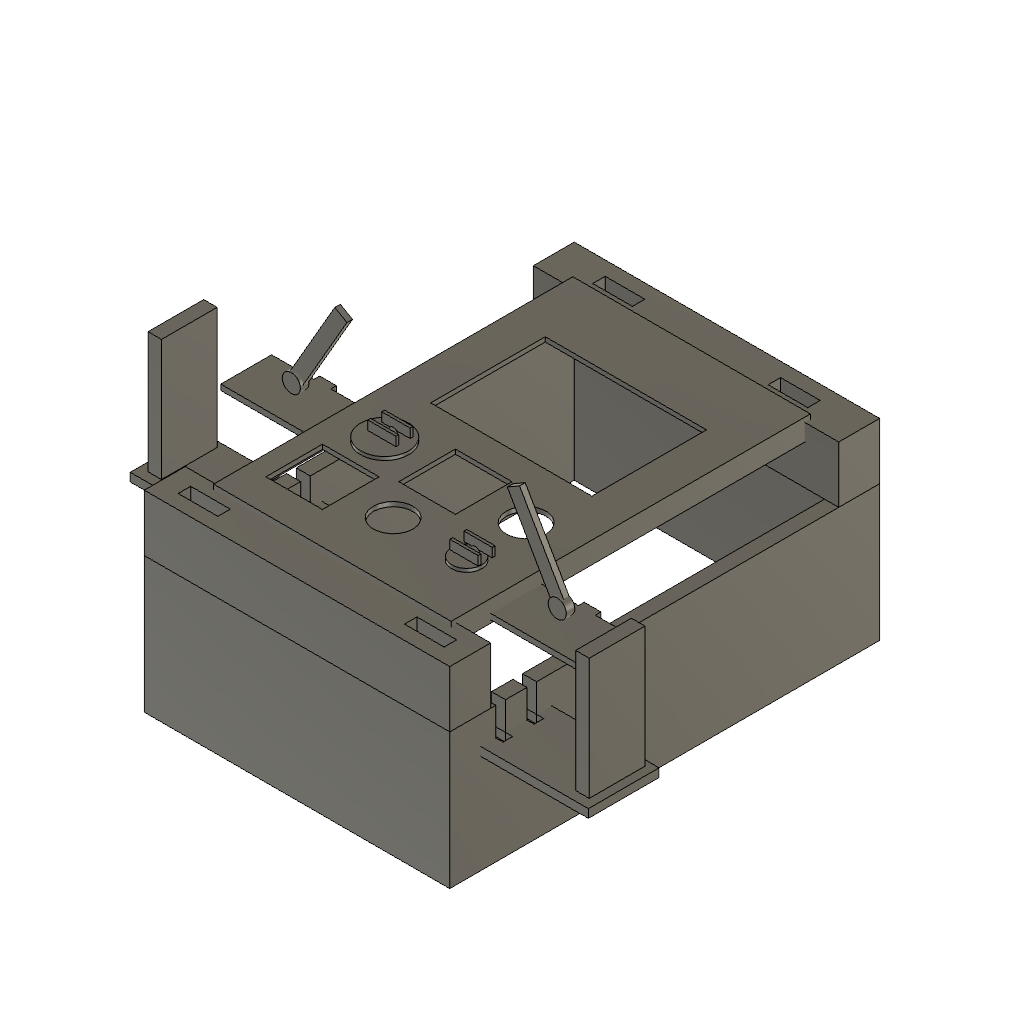
VS-MGE20_Case_SG90_square20 (Autodesk Fusion 360 design; units mm, degrees)
Autodesk Fusion 360 part; units mm, degrees
(part 1 of 2)
sketch "スケッチ1" plane through (0, 0, 0) normal (0, 0, 1) x (1, 0, 0) in component "VS-MGE20 Case Assembly"
  line L0 (-42, -63.5) -> (42, -63.5)
  line L1 (42, -63.5) -> (42, 63.5)
  line L2 (42, 63.5) -> (-42, 63.5)
  line L3 (-42, 63.5) -> (-42, -63.5)
  line L4 (-28.5, -0.25) -> (28.5, -0.25)
  line L5 (28.5, -0.25) -> (28.5, 40.25)
  line L6 (28.5, 40.25) -> (-28.5, 40.25)
  line L7 (-28.5, 40.25) -> (-28.5, -0.25)
  circle A0 centre (-25, -20) radius 8
  circle A1 centre (26, -42) radius 4.8
  line L8 (-33, -34.55) -> (-16, -34.55)
  line L9 (-16, -34.55) -> (-16, -33.45)
  line L10 (-16, -33.45) -> (-33, -33.45)
  line L11 (-33, -33.45) -> (-33, -34.55)
  line L12 (-33, -37.55) -> (-16, -37.55)
  line L13 (-16, -37.55) -> (-16, -36.45)
  line L14 (-16, -36.45) -> (-33, -36.45)
  line L15 (-33, -36.45) -> (-33, -37.55)
  line L16 (-33, -40.55) -> (-16, -40.55)
  line L17 (-16, -40.55) -> (-16, -39.45)
  line L18 (-16, -39.45) -> (-33, -39.45)
  line L19 (-33, -39.45) -> (-33, -40.55)
  line L20 (-33, -43.55) -> (-16, -43.55)
  line L21 (-16, -43.55) -> (-16, -42.45)
  line L22 (-16, -42.45) -> (-33, -42.45)
  line L23 (-33, -42.45) -> (-33, -43.55)
  line L24 (-33, -46.55) -> (-16, -46.55)
  line L25 (-16, -46.55) -> (-16, -45.45)
  line L26 (-16, -45.45) -> (-33, -45.45)
  line L27 (-33, -45.45) -> (-33, -46.55)
  line L28 (-33, -49.55) -> (-16, -49.55)
  line L29 (-16, -49.55) -> (-16, -48.45)
  line L30 (-16, -48.45) -> (-33, -48.45)
  line L31 (-33, -48.45) -> (-33, -49.55)
extrude "1.6 mm face plate" add sketch "スケッチ1" along normal blind 1.6 makes body 1 in component "VS-MGE20 Case Assembly"
sketch "スケッチ2" plane through (0, 0, 0) normal (0, 0, 1) x (1, 0, 0) in component "VS-MGE20 Case Assembly"
  line L0 (-42, -63.5) -> (42, -63.5)
  line L1 (42, -63.5) -> (42, 63.5)
  line L2 (42, 63.5) -> (-42, 63.5)
  line L3 (-42, 63.5) -> (-42, -63.5)
  line L4 (-40.5, -62) -> (40.5, -62)
  line L5 (40.5, -62) -> (40.5, 62)
  line L6 (40.5, 62) -> (-40.5, 62)
  line L7 (-40.5, 62) -> (-40.5, -62)
extrude "6 mm rear retaining rim" add sketch "スケッチ2" against normal blind 6 bodies 1 in component "VS-MGE20 Case Assembly"
ref_plane "作業平面1" through (0, 0, -68) normal (0, 0, 1) x (1, 0, 0) in component "VS-MGE20 Case Assembly"
sketch "スケッチ3" plane through (0, 0, -68) normal (0, 0, 1) x (1, 0, 0) in component "VS-MGE20 Case Assembly"
  line L0 (-54, -76) -> (54, -76)
  line L1 (54, -76) -> (54, 76)
  line L2 (54, 76) -> (-54, 76)
  line L3 (-54, 76) -> (-54, -76)
  line L4 (-49, -71) -> (49, -71)
  line L5 (49, -71) -> (49, 71)
  line L6 (49, 71) -> (-49, 71)
  line L7 (-49, 71) -> (-49, -71)
ref_plane "作業平面2" through (0, 0, -20) normal (0, 0, 1) x (1, 0, 0) in component "VS-MGE20 Case Assembly"
sketch "スケッチ4" plane through (0, 0, -20) normal (0, 0, 1) x (1, 0, 0) in component "VS-MGE20 Case Assembly"
  line L0 (-54, 61.5) -> (54, 61.5)
  line L1 (54, 61.5) -> (54, 76)
  line L2 (54, 76) -> (-54, 76)
  line L3 (-54, 76) -> (-54, 61.5)
  line L4 (-54, -76) -> (54, -76)
  line L5 (54, -76) -> (54, -61.5)
  line L6 (54, -61.5) -> (-54, -61.5)
  line L7 (-54, -61.5) -> (-54, -76)
extrude "Top and bottom support bridges" add sketch "スケッチ4" along normal blind 20 separate body contours L0 L1 L2 L3 makes body 2 in component "VS-MGE20 Case Assembly"
ref_plane "作業平面3" through (0, 0, -23) normal (0, 0, 1) x (1, 0, 0) in component "VS-MGE20 Case Assembly"
sketch "スケッチ5" plane through (0, 0, -23) normal (0, 0, 1) x (1, 0, 0) in component "VS-MGE20 Case Assembly"
  line L0 (-90, -24) -> (-44, -24)
  line L1 (-44, -24) -> (-44, 28)
  line L2 (-44, 28) -> (-90, 28)
  line L3 (-90, 28) -> (-90, -24)
  line L4 (44, -46) -> (90, -46)
  line L5 (90, -46) -> (90, 6)
  line L6 (90, 6) -> (44, 6)
  line L7 (44, 6) -> (44, -46)
  circle A0 centre (-84, -18) radius 1.7
  circle A1 centre (-50, 20) radius 1.7
  circle A2 centre (-84, -56) radius 1.7
  circle A3 centre (-50, -22) radius 1.7
  circle A4 centre (84, -40) radius 1.7
  circle A5 centre (50, 2) radius 1.7
  circle A6 centre (84, -78) radius 1.7
  circle A7 centre (50, -44) radius 1.7
ref_plane "作業平面4" through (0, 0, -20) normal (0, 0, 1) x (1, 0, 0) in component "VS-MGE20 Case Assembly"
sketch "スケッチ6" plane through (0, 0, -20) normal (0, 0, 1) x (1, 0, 0) in component "VS-MGE20 Case Assembly"
  line L0 (-54, -76) -> (54, -76)
  line L1 (54, -76) -> (54, -61.5)
  line L2 (54, -61.5) -> (-54, -61.5)
  line L3 (-54, -61.5) -> (-54, -76)
ref_plane "作業平面5" through (0, 0, -23) normal (0, 0, 1) x (1, 0, 0) in component "VS-MGE20 Case Assembly"
sketch "スケッチ7" plane through (0, 0, -23) normal (0, 0, 1) x (1, 0, 0) in component "VS-MGE20 Case Assembly"
  line L0 (44, -46) -> (90, -46)
  line L1 (90, -46) -> (90, 6)
  line L2 (90, 6) -> (44, 6)
  line L3 (44, 6) -> (44, -46)
  circle A0 centre (84, -40) radius 1.7
  circle A1 centre (50, 2) radius 1.7
  circle A2 centre (84, -78) radius 1.7
  circle A3 centre (50, -44) radius 1.7
ref_plane "作業平面6" through (0, 0, -19.7) normal (0, 0, 1) x (1, 0, 0) in component "VS-MGE20 Case Assembly"
sketch "スケッチ8" plane through (0, 0, -19.7) normal (0, 0, 1) x (1, 0, 0) in component "VS-MGE20 Case Assembly"
  line L0 (-87.35, -20) -> (-46.65, -20)
  line L1 (-46.65, -20) -> (-46.65, 22.9)
  line L2 (-46.65, 22.9) -> (-87.35, 22.9)
  line L3 (-87.35, 22.9) -> (-87.35, -20)
ref_plane "作業平面7" through (0, 0, -19.7) normal (0, 0, 1) x (1, 0, 0) in component "VS-MGE20 Case Assembly"
sketch "スケッチ9" plane through (0, 0, -19.7) normal (0, 0, 1) x (1, 0, 0) in component "VS-MGE20 Case Assembly"
  line L0 (46.65, -42) -> (87.35, -42)
  line L1 (87.35, -42) -> (87.35, 0.9)
  line L2 (87.35, 0.9) -> (46.65, 0.9)
  line L3 (46.65, 0.9) -> (46.65, -42)
ref_plane "作業平面8" through (0, 18, 0) normal (0, 1, 0) x (0, 0, 1) in component "VS-MGE20 Case Assembly"
sketch "スケッチ10" plane through (0, 18, 0) normal (0, 1, 0) x (1, 0, 0) in component "VS-MGE20 Case Assembly"
  line L0 (-55.3119, -8.8999) -> (-25.3119, 0.9501)
  line L1 (-25.3119, 0.9501) -> (-24.6881, -0.9501)
  line L2 (-24.6881, -0.9501) -> (-54.6881, -10.8001)
  line L3 (-54.6881, -10.8001) -> (-55.3119, -8.8999)
ref_plane "作業平面9" through (0, 40, 0) normal (0, 1, 0) x (0, 0, 1) in component "VS-MGE20 Case Assembly"
sketch "スケッチ11" plane through (0, 40, 0) normal (0, 1, 0) x (1, 0, 0) in component "VS-MGE20 Case Assembly"
  line L0 (54.6784, -10.7969) -> (25.6784, -0.9469)
  line L1 (25.6784, -0.9469) -> (26.3216, 0.9469)
  line L2 (26.3216, 0.9469) -> (55.3216, -8.9031)
  line L3 (55.3216, -8.9031) -> (54.6784, -10.7969)
ref_plane "作業平面10" through (0, 0, -0.3) normal (0, 0, 1) x (1, 0, 0) in component "VS-MGE20 Case Assembly"
sketch "スケッチ12" plane through (0, 0, -0.3) normal (0, 0, 1) x (1, 0, 0) in component "VS-MGE20 Case Assembly"
  circle A0 centre (-25, -20) radius 3.5
  circle A1 centre (26, -42) radius 2.8
ref_plane "作業平面11" through (0, 0, 1.6) normal (0, 0, 1) x (1, 0, 0) in component "VS-MGE20 Case Assembly"
sketch "スケッチ13" plane through (0, 0, 1.6) normal (0, 0, 1) x (1, 0, 0) in component "VS-MGE20 Case Assembly"
  line L0 (-54.6696, -13.5219) -> (-24.6696, -17.5219)
  line L1 (-24.6696, -17.5219) -> (-25.3304, -22.4781)
  line L2 (-25.3304, -22.4781) -> (-55.3304, -18.4781)
  line L3 (-55.3304, -18.4781) -> (-54.6696, -13.5219)
  line L4 (55.3416, -40.4766) -> (26.3416, -44.4766)
  line L5 (26.3416, -44.4766) -> (25.6584, -39.5234)
  line L6 (25.6584, -39.5234) -> (54.6584, -35.5234)
  line L7 (54.6584, -35.5234) -> (55.3416, -40.4766)
ref_plane "作業平面12" through (0, 0, 0) normal (0, 0, 1) x (1, 0, 0) in component "VS-MGE20 Case Assembly"
sketch "スケッチ14" plane through (0, 0, 0) normal (0, 0, 1) x (1, 0, 0) in component "VS-MGE20 Case Assembly"
  circle A0 centre (-55, -16) radius 4.2
  circle A1 centre (55, -38) radius 4.2
ref_plane "作業平面13" through (0, 0, -0.3) normal (0, 0, 1) x (1, 0, 0) in component "VS-MGE20 Case Assembly"
sketch "スケッチ15" plane through (0, 0, -0.3) normal (0, 0, 1) x (1, 0, 0) in component "VS-MGE20 Case Assembly"
  circle A0 centre (-25, -20) radius 3.5
  circle A1 centre (26, -42) radius 2.8
ref_plane "作業平面14" through (0, 0, -20) normal (0, 0, 1) x (1, 0, 0) in component "VS-MGE20 Case Assembly"
sketch "スケッチ16" plane through (0, 0, -20) normal (0, 0, 1) x (1, 0, 0) in component "VS-MGE20 Case Assembly"
  line L0 (-38, -70.95) -> (-24, -70.95)
  line L1 (-24, -70.95) -> (-24, -66.55)
  line L2 (-24, -66.55) -> (-38, -66.55)
  line L3 (-38, -66.55) -> (-38, -70.95)
  line L4 (24, -70.95) -> (38, -70.95)
  line L5 (38, -70.95) -> (38, -66.55)
  line L6 (38, -66.55) -> (24, -66.55)
  line L7 (24, -66.55) -> (24, -70.95)
  line L8 (-38, 66.55) -> (-24, 66.55)
  line L9 (-24, 66.55) -> (-24, 70.95)
  line L10 (-24, 70.95) -> (-38, 70.95)
  line L11 (-38, 70.95) -> (-38, 66.55)
  line L12 (24, 66.55) -> (38, 66.55)
  line L13 (38, 66.55) -> (38, 70.95)
  line L14 (38, 70.95) -> (24, 70.95)
  line L15 (24, 70.95) -> (24, 66.55)
ref_plane "作業平面15" through (0, 0, 1.6) normal (0, 0, 1) x (1, 0, 0) in component "VS-MGE20 Case Assembly"
sketch "スケッチ17" plane through (0, 0, 1.6) normal (0, 0, 1) x (1, 0, 0) in component "VS-MGE20 Case Assembly"
  line L0 (55.3416, -40.4766) -> (26.3416, -44.4766)
  line L1 (26.3416, -44.4766) -> (25.6584, -39.5234)
  line L2 (25.6584, -39.5234) -> (54.6584, -35.5234)
  line L3 (54.6584, -35.5234) -> (55.3416, -40.4766)
ref_plane "作業平面16" through (0, 0, 0) normal (0, 0, 1) x (1, 0, 0) in component "VS-MGE20 Case Assembly"
sketch "スケッチ18" plane through (0, 0, 0) normal (0, 0, 1) x (1, 0, 0) in component "VS-MGE20 Case Assembly"
  circle A0 centre (55, -38) radius 4.2
ref_plane "作業平面17" through (0, 0, -0.3) normal (0, 0, 1) x (1, 0, 0) in component "VS-MGE20 Case Assembly"
sketch "スケッチ19" plane through (0, 0, -0.3) normal (0, 0, 1) x (1, 0, 0) in component "VS-MGE20 Case Assembly"
  circle A0 centre (26, -42) radius 2.8
ref_plane "作業平面18" through (0, 0, -20) normal (0, 0, 1) x (1, 0, 0) in component "VS-MGE20 Case Assembly"
sketch "スケッチ20" plane through (0, 0, -20) normal (0, 0, 1) x (1, 0, 0) in component "VS-MGE20 Case Assembly"
  line L0 (24, -70.95) -> (38, -70.95)
  line L1 (38, -70.95) -> (38, -66.55)
  line L2 (38, -66.55) -> (24, -66.55)
  line L3 (24, -66.55) -> (24, -70.95)
ref_plane "作業平面19" through (0, 0, -20) normal (0, 0, 1) x (1, 0, 0) in component "VS-MGE20 Case Assembly"
sketch "スケッチ21" plane through (0, 0, -20) normal (0, 0, 1) x (1, 0, 0) in component "VS-MGE20 Case Assembly"
  line L0 (-38, 66.55) -> (-24, 66.55)
  line L1 (-24, 66.55) -> (-24, 70.95)
  line L2 (-24, 70.95) -> (-38, 70.95)
  line L3 (-38, 70.95) -> (-38, 66.55)
extrude "押し出し24" cut sketch "スケッチ21" along normal blind 22 bodies 2 in component "VS-MGE20 Case Assembly"
ref_plane "作業平面20" through (0, 0, -20) normal (0, 0, 1) x (1, 0, 0) in component "VS-MGE20 Case Assembly"
sketch "スケッチ22" plane through (0, 0, -20) normal (0, 0, 1) x (1, 0, 0) in component "VS-MGE20 Case Assembly"
  line L0 (24, 66.55) -> (38, 66.55)
  line L1 (38, 66.55) -> (38, 70.95)
  line L2 (38, 70.95) -> (24, 70.95)
  line L3 (24, 70.95) -> (24, 66.55)
extrude "押し出し25" cut sketch "スケッチ22" along normal blind 22 bodies 2 in component "VS-MGE20 Case Assembly"
ref_plane "作業平面21" through (0, 0, -0.3) normal (0, 0, 1) x (1, 0, 0) in component "VS-MGE20 Case Assembly"
sketch "スケッチ23" plane through (0, 0, -0.3) normal (0, 0, 1) x (1, 0, 0) in component "VS-MGE20 Case Assembly"
  circle A0 centre (-25, -20) radius 3.5
ref_plane "作業平面22" through (0, 0, -0.3) normal (0, 0, 1) x (1, 0, 0) in component "VS-MGE20 Case Assembly"
sketch "スケッチ24" plane through (0, 0, -0.3) normal (0, 0, 1) x (1, 0, 0) in component "VS-MGE20 Case Assembly"
  circle A0 centre (26, -42) radius 2.8
ref_plane "作業平面23" through (0, 0, 1.6) normal (0, 0, 1) x (1, 0, 0) in component "VS-MGE20 Case Assembly"
sketch "スケッチ25" plane through (0, 0, 1.6) normal (0, 0, 1) x (1, 0, 0) in component "VS-MGE20 Case Assembly"
  circle A0 centre (-25, -20) radius 8.5
ref_plane "作業平面24" through (0, 0, 1.6) normal (0, 0, 1) x (1, 0, 0) in component "VS-MGE20 Case Assembly"
sketch "スケッチ26" plane through (0, 0, 1.6) normal (0, 0, 1) x (1, 0, 0) in component "VS-MGE20 Case Assembly"
  circle A0 centre (26, -42) radius 5.3
ref_plane "作業平面25" through (0, 0, -33) normal (0, 0, 1) x (1, 0, 0) in component "VS-MGE20 Case Assembly"
sketch "スケッチ27" plane through (0, 0, -33) normal (0, 0, 1) x (1, 0, 0) in component "VS-MGE20 Case Assembly"
  line L0 (-92, -43) -> (-42, -43)
  line L1 (-42, -43) -> (-42, -18)
  line L2 (-42, -18) -> (-92, -18)
  line L3 (-92, -18) -> (-92, -43)
ref_plane "作業平面26" through (0, 0, -33) normal (0, 0, 1) x (1, 0, 0) in component "VS-MGE20 Case Assembly"
sketch "スケッチ28" plane through (0, 0, -33) normal (0, 0, 1) x (1, 0, 0) in component "VS-MGE20 Case Assembly"
  line L0 (-89.7, -41) -> (-86.3, -41)
  line L1 (-86.3, -41) -> (-86.3, -34)
  line L2 (-86.3, -34) -> (-89.7, -34)
  line L3 (-89.7, -34) -> (-89.7, -41)
  line L4 (-89.7, -27) -> (-86.3, -27)
  line L5 (-86.3, -27) -> (-86.3, -20)
  line L6 (-86.3, -20) -> (-89.7, -20)
  line L7 (-89.7, -20) -> (-89.7, -27)
  line L8 (-47.7, -41) -> (-44.3, -41)
  line L9 (-44.3, -41) -> (-44.3, -34)
  line L10 (-44.3, -34) -> (-47.7, -34)
  line L11 (-47.7, -34) -> (-47.7, -41)
  line L12 (-47.7, -27) -> (-44.3, -27)
  line L13 (-44.3, -27) -> (-44.3, -20)
  line L14 (-44.3, -20) -> (-47.7, -20)
  line L15 (-47.7, -20) -> (-47.7, -27)
ref_plane "作業平面27" through (0, 0, -30) normal (0, 0, 1) x (1, 0, 0) in component "VS-MGE20 Case Assembly"
sketch "スケッチ29" plane through (0, 0, -30) normal (0, 0, 1) x (1, 0, 0) in component "VS-MGE20 Case Assembly"
  line L0 (-92, -40.7) -> (-87, -40.7)
  line L1 (-87, -40.7) -> (-87, -19)
  line L2 (-87, -19) -> (-92, -19)
  line L3 (-92, -19) -> (-92, -40.7)
ref_plane "作業平面28" through (0, 0, -30) normal (0, 0, 1) x (1, 0, 0) in component "VS-MGE20 Case Assembly"
sketch "スケッチ30" plane through (0, 0, -30) normal (0, 0, 1) x (1, 0, 0) in component "VS-MGE20 Case Assembly"
  line L0 (-46.5, -40.7) -> (-43.5, -40.7)
  line L1 (-43.5, -40.7) -> (-43.5, -19)
  line L2 (-43.5, -19) -> (-46.5, -19)
  line L3 (-46.5, -19) -> (-46.5, -40.7)
ref_plane "作業平面29" through (0, 0, -30) normal (0, 0, 1) x (1, 0, 0) in component "VS-MGE20 Case Assembly"
sketch "スケッチ31" plane through (0, 0, -30) normal (0, 0, 1) x (1, 0, 0) in component "VS-MGE20 Case Assembly"
  line L0 (-84.2, -39.7) -> (-43.5, -39.7)
  line L1 (-43.5, -39.7) -> (-43.5, -20)
  line L2 (-43.5, -20) -> (-84.2, -20)
  line L3 (-84.2, -20) -> (-84.2, -39.7)
extrude "押し出し37" add sketch "スケッチ31" along normal blind 42.9 separate body makes body 3 in component "VS-MGE20 Case Assembly"
ref_plane "作業平面30" through (0, 20, 0) normal (0, 1, 0) x (0, 0, 1) in component "VS-MGE20 Case Assembly"
sketch "スケッチ32" plane through (0, 20, 0) normal (0, 1, 0) x (1, 0, 0) in component "VS-MGE20 Case Assembly"
  circle A0 centre (-58, 2.8) radius 3.2
ref_plane "作業平面31" through (0, 18.5, 0) normal (0, 1, 0) x (0, 0, 1) in component "VS-MGE20 Case Assembly"
sketch "スケッチ33" plane through (0, 18.5, 0) normal (0, 1, 0) x (1, 0, 0) in component "VS-MGE20 Case Assembly"
  line L0 (-60.1651, 4.05) -> (-43.6651, 32.63)
  line L1 (-43.6651, 32.63) -> (-39.3349, 30.13)
  line L2 (-39.3349, 30.13) -> (-55.8349, 1.55)
  line L3 (-55.8349, 1.55) -> (-60.1651, 4.05)
ref_plane "作業平面32" through (0, 18.5, 0) normal (0, 1, 0) x (0, 0, 1) in component "VS-MGE20 Case Assembly"
sketch "スケッチ34" plane through (0, 18.5, 0) normal (0, 1, 0) x (1, 0, 0) in component "VS-MGE20 Case Assembly"
  line L0 (-58, 5.3) -> (-25, 5.3)
  line L1 (-25, 5.3) -> (-25, 0.3)
  line L2 (-25, 0.3) -> (-58, 0.3)
  line L3 (-58, 0.3) -> (-58, 5.3)
ref_plane "作業平面33" through (0, 0, -0.3) normal (0, 0, 1) x (1, 0, 0) in component "VS-MGE20 Case Assembly"
sketch "スケッチ35" plane through (0, 0, -0.3) normal (0, 0, 1) x (1, 0, 0) in component "VS-MGE20 Case Assembly"
  circle A0 centre (-25, -20) radius 3.5
extrude "押し出し41" add sketch "スケッチ35" along normal blind 1.9 separate body makes body 4 in component "VS-MGE20 Case Assembly"
ref_plane "作業平面34" through (0, 0, 1.6) normal (0, 0, 1) x (1, 0, 0) in component "VS-MGE20 Case Assembly"
sketch "スケッチ36" plane through (0, 0, 1.6) normal (0, 0, 1) x (1, 0, 0) in component "VS-MGE20 Case Assembly"
  circle A0 centre (-25, -20) radius 8.5
extrude "押し出し42" add sketch "スケッチ36" along normal blind 1.2 separate body makes body 5 in component "VS-MGE20 Case Assembly"
ref_plane "作業平面35" through (0, 0, 0) normal (0, 0, 1) x (1, 0, 0) in component "VS-MGE20 Case Assembly"
sketch "スケッチ37" plane through (0, 0, 0) normal (0, 0, 1) x (1, 0, 0) in component "VS-MGE20 Case Assembly"
  circle A0 centre (-25, -20) radius 7
  circle A1 centre (-25, -20) radius 3.8
extrude "押し出し43" add sketch "スケッチ37" along normal blind 1.6 separate body makes body 6 in component "VS-MGE20 Case Assembly"
ref_plane "作業平面36" through (0, 0, 2.8) normal (0, 0, 1) x (1, 0, 0) in component "VS-MGE20 Case Assembly"
sketch "スケッチ38" plane through (0, 0, 2.8) normal (0, 0, 1) x (1, 0, 0) in component "VS-MGE20 Case Assembly"
  line L0 (-30, -23.8) -> (-20, -23.8)
  line L1 (-20, -23.8) -> (-20, -22.6)
  line L2 (-20, -22.6) -> (-30, -22.6)
  line L3 (-30, -22.6) -> (-30, -23.8)
  line L4 (-30, -17.4) -> (-20, -17.4)
  line L5 (-20, -17.4) -> (-20, -16.2)
  line L6 (-20, -16.2) -> (-30, -16.2)
  line L7 (-30, -16.2) -> (-30, -17.4)
ref_plane "作業平面37" through (0, 0, -33) normal (0, 0, 1) x (1, 0, 0) in component "VS-MGE20 Case Assembly"
sketch "スケッチ39" plane through (0, 0, -33) normal (0, 0, 1) x (1, 0, 0) in component "VS-MGE20 Case Assembly"
  line L0 (42, -65) -> (92, -65)
  line L1 (92, -65) -> (92, -40)
  line L2 (92, -40) -> (42, -40)
  line L3 (42, -40) -> (42, -65)
ref_plane "作業平面38" through (0, 0, -33) normal (0, 0, 1) x (1, 0, 0) in component "VS-MGE20 Case Assembly"
sketch "スケッチ40" plane through (0, 0, -33) normal (0, 0, 1) x (1, 0, 0) in component "VS-MGE20 Case Assembly"
  line L0 (44.3, -63) -> (47.7, -63)
  line L1 (47.7, -63) -> (47.7, -56)
  line L2 (47.7, -56) -> (44.3, -56)
  line L3 (44.3, -56) -> (44.3, -63)
  line L4 (44.3, -49) -> (47.7, -49)
  line L5 (47.7, -49) -> (47.7, -42)
  line L6 (47.7, -42) -> (44.3, -42)
  line L7 (44.3, -42) -> (44.3, -49)
  line L8 (86.3, -63) -> (89.7, -63)
  line L9 (89.7, -63) -> (89.7, -56)
  line L10 (89.7, -56) -> (86.3, -56)
  line L11 (86.3, -56) -> (86.3, -63)
  line L12 (86.3, -49) -> (89.7, -49)
  line L13 (89.7, -49) -> (89.7, -42)
  line L14 (89.7, -42) -> (86.3, -42)
  line L15 (86.3, -42) -> (86.3, -49)
ref_plane "作業平面39" through (0, 0, -30) normal (0, 0, 1) x (1, 0, 0) in component "VS-MGE20 Case Assembly"
sketch "スケッチ41" plane through (0, 0, -30) normal (0, 0, 1) x (1, 0, 0) in component "VS-MGE20 Case Assembly"
  line L0 (42, -62.7) -> (47, -62.7)
  line L1 (47, -62.7) -> (47, -41)
  line L2 (47, -41) -> (42, -41)
  line L3 (42, -41) -> (42, -62.7)
ref_plane "作業平面40" through (0, 0, -30) normal (0, 0, 1) x (1, 0, 0) in component "VS-MGE20 Case Assembly"
sketch "スケッチ42" plane through (0, 0, -30) normal (0, 0, 1) x (1, 0, 0) in component "VS-MGE20 Case Assembly"
  line L0 (87.5, -62.7) -> (90.5, -62.7)
  line L1 (90.5, -62.7) -> (90.5, -41)
  line L2 (90.5, -41) -> (87.5, -41)
  line L3 (87.5, -41) -> (87.5, -62.7)
ref_plane "作業平面41" through (0, 0, -30) normal (0, 0, 1) x (1, 0, 0) in component "VS-MGE20 Case Assembly"
sketch "スケッチ43" plane through (0, 0, -30) normal (0, 0, 1) x (1, 0, 0) in component "VS-MGE20 Case Assembly"
  line L0 (43.5, -61.7) -> (84.2, -61.7)
  line L1 (84.2, -61.7) -> (84.2, -42)
  line L2 (84.2, -42) -> (43.5, -42)
  line L3 (43.5, -42) -> (43.5, -61.7)
extrude "押し出し53" add sketch "スケッチ43" along normal blind 42.9 separate body makes body 7 in component "VS-MGE20 Case Assembly"
ref_plane "作業平面42" through (0, 42, 0) normal (0, 1, 0) x (0, 0, 1) in component "VS-MGE20 Case Assembly"
sketch "スケッチ44" plane through (0, 42, 0) normal (0, 1, 0) x (1, 0, 0) in component "VS-MGE20 Case Assembly"
  circle A0 centre (58, 2.8) radius 3.2
ref_plane "作業平面43" through (0, 40.5, 0) normal (0, 1, 0) x (0, 0, 1) in component "VS-MGE20 Case Assembly"
sketch "スケッチ45" plane through (0, 40.5, 0) normal (0, 1, 0) x (1, 0, 0) in component "VS-MGE20 Case Assembly"
  line L0 (55.835, 1.5499) -> (39.835, 29.2599)
  line L1 (39.835, 29.2599) -> (44.165, 31.7601)
  line L2 (44.165, 31.7601) -> (60.165, 4.0501)
  line L3 (60.165, 4.0501) -> (55.835, 1.5499)
ref_plane "作業平面44" through (0, 40.5, 0) normal (0, 1, 0) x (0, 0, 1) in component "VS-MGE20 Case Assembly"
sketch "スケッチ46" plane through (0, 40.5, 0) normal (0, 1, 0) x (1, 0, 0) in component "VS-MGE20 Case Assembly"
  line L0 (58, 0.3) -> (26, 0.3)
  line L1 (26, 0.3) -> (26, 5.3)
  line L2 (26, 5.3) -> (58, 5.3)
  line L3 (58, 5.3) -> (58, 0.3)
ref_plane "作業平面45" through (0, 0, -0.3) normal (0, 0, 1) x (1, 0, 0) in component "VS-MGE20 Case Assembly"
sketch "スケッチ47" plane through (0, 0, -0.3) normal (0, 0, 1) x (1, 0, 0) in component "VS-MGE20 Case Assembly"
  circle A0 centre (26, -42) radius 2.8
extrude "押し出し57" add sketch "スケッチ47" along normal blind 1.9 separate body makes body 8 in component "VS-MGE20 Case Assembly"
ref_plane "作業平面46" through (0, 0, 1.6) normal (0, 0, 1) x (1, 0, 0) in component "VS-MGE20 Case Assembly"
sketch "スケッチ48" plane through (0, 0, 1.6) normal (0, 0, 1) x (1, 0, 0) in component "VS-MGE20 Case Assembly"
  circle A0 centre (26, -42) radius 5.3
extrude "押し出し58" add sketch "スケッチ48" along normal blind 1.2 separate body makes body 9 in component "VS-MGE20 Case Assembly"
ref_plane "作業平面47" through (0, 0, 0) normal (0, 0, 1) x (1, 0, 0) in component "VS-MGE20 Case Assembly"
sketch "スケッチ49" plane through (0, 0, 0) normal (0, 0, 1) x (1, 0, 0) in component "VS-MGE20 Case Assembly"
  circle A0 centre (26, -42) radius 4.2
  circle A1 centre (26, -42) radius 3
extrude "押し出し59" add sketch "スケッチ49" along normal blind 1.6 separate body makes body 10 in component "VS-MGE20 Case Assembly"
ref_plane "作業平面48" through (0, 0, 2.8) normal (0, 0, 1) x (1, 0, 0) in component "VS-MGE20 Case Assembly"
sketch "スケッチ50" plane through (0, 0, 2.8) normal (0, 0, 1) x (1, 0, 0) in component "VS-MGE20 Case Assembly"
  line L0 (21, -45.8) -> (31, -45.8)
  line L1 (31, -45.8) -> (31, -44.6)
  line L2 (31, -44.6) -> (21, -44.6)
  line L3 (21, -44.6) -> (21, -45.8)
  line L4 (21, -39.4) -> (31, -39.4)
  line L5 (31, -39.4) -> (31, -38.2)
  line L6 (31, -38.2) -> (21, -38.2)
  line L7 (21, -38.2) -> (21, -39.4)
ref_plane "作業平面49" through (0, -20, 0) normal (0, 1, 0) x (0, 0, 1) in component "VS-MGE20 Case Assembly"
sketch "スケッチ51" plane through (0, -20, 0) normal (0, 1, 0) x (1, 0, 0) in component "VS-MGE20 Case Assembly"
  circle A0 centre (-58, -2.8) radius 3.2
ref_plane "作業平面50" through (0, -18.5, 0) normal (0, 1, 0) x (0, 0, 1) in component "VS-MGE20 Case Assembly"
sketch "スケッチ52" plane through (0, -18.5, 0) normal (0, 1, 0) x (1, 0, 0) in component "VS-MGE20 Case Assembly"
  line L0 (-60.1655, -4.0493) -> (-43.6655, -32.6493)
  line L1 (-43.6655, -32.6493) -> (-39.3345, -30.1507)
  line L2 (-39.3345, -30.1507) -> (-55.8345, -1.5507)
  line L3 (-55.8345, -1.5507) -> (-60.1655, -4.0493)
ref_plane "作業平面51" through (0, -18.5, 0) normal (0, 1, 0) x (0, 0, 1) in component "VS-MGE20 Case Assembly"
sketch "スケッチ53" plane through (0, -18.5, 0) normal (0, 1, 0) x (1, 0, 0) in component "VS-MGE20 Case Assembly"
  line L0 (-58, -5.3) -> (-25, -5.3)
  line L1 (-25, -5.3) -> (-25, -0.3)
  line L2 (-25, -0.3) -> (-58, -0.3)
  line L3 (-58, -0.3) -> (-58, -5.3)
ref_plane "作業平面52" through (0, -42, 0) normal (0, 1, 0) x (0, 0, 1) in component "VS-MGE20 Case Assembly"
sketch "スケッチ54" plane through (0, -42, 0) normal (0, 1, 0) x (1, 0, 0) in component "VS-MGE20 Case Assembly"
  circle A0 centre (58, -2.8) radius 3.2
ref_plane "作業平面53" through (0, -40.5, 0) normal (0, 1, 0) x (0, 0, 1) in component "VS-MGE20 Case Assembly"
sketch "スケッチ55" plane through (0, -40.5, 0) normal (0, 1, 0) x (1, 0, 0) in component "VS-MGE20 Case Assembly"
  line L0 (55.8345, -1.5507) -> (39.3345, -30.1507)
  line L1 (39.3345, -30.1507) -> (43.6655, -32.6493)
  line L2 (43.6655, -32.6493) -> (60.1655, -4.0493)
  line L3 (60.1655, -4.0493) -> (55.8345, -1.5507)
ref_plane "作業平面54" through (0, -40.5, 0) normal (0, 1, 0) x (0, 0, 1) in component "VS-MGE20 Case Assembly"
sketch "スケッチ56" plane through (0, -40.5, 0) normal (0, 1, 0) x (1, 0, 0) in component "VS-MGE20 Case Assembly"
  line L0 (58, -0.3) -> (26, -0.3)
  line L1 (26, -0.3) -> (26, -5.3)
  line L2 (26, -5.3) -> (58, -5.3)
  line L3 (58, -5.3) -> (58, -0.3)
ref_plane "作業平面55" through (0, 0, -30) normal (0, 0, 1) x (1, 0, 0) in component "VS-MGE20 Case Assembly"
sketch "スケッチ57" plane through (0, 0, -30) normal (0, 0, 1) x (1, 0, 0) in component "VS-MGE20 Case Assembly"
  line L0 (-89, -39.7) -> (-84.2, -39.7)
  line L1 (-84.2, -39.7) -> (-84.2, -20)
  line L2 (-84.2, -20) -> (-89, -20)
  line L3 (-89, -20) -> (-89, -39.7)
extrude "押し出し68" add sketch "スケッチ57" along normal blind 42.9 separate body makes body 11 in component "VS-MGE20 Case Assembly"
ref_plane "作業平面56" through (0, -20, 0) normal (0, 1, 0) x (0, 0, 1) in component "VS-MGE20 Case Assembly"
sketch "スケッチ58" plane through (0, -20, 0) normal (0, 1, 0) x (1, 0, 0) in component "VS-MGE20 Case Assembly"
  circle A0 centre (-58, -2.8) radius 3.2
extrude "押し出し69" add sketch "スケッチ58" along normal blind 3 separate body makes body 12 in component "VS-MGE20 Case Assembly"
ref_plane "作業平面57" through (0, -17, 0) normal (0, 1, 0) x (0, 0, 1) in component "VS-MGE20 Case Assembly"
sketch "スケッチ59" plane through (0, -17, 0) normal (0, 1, 0) x (1, 0, 0) in component "VS-MGE20 Case Assembly"
  line L0 (-60.1655, -4.0493) -> (-43.6655, -32.6493)
  line L1 (-43.6655, -32.6493) -> (-39.3345, -30.1507)
  line L2 (-39.3345, -30.1507) -> (-55.8345, -1.5507)
  line L3 (-55.8345, -1.5507) -> (-60.1655, -4.0493)
extrude "押し出し70" add sketch "スケッチ59" against normal blind 2 separate body makes body 13 in component "VS-MGE20 Case Assembly"
ref_plane "作業平面58" through (0, -17, 0) normal (0, 1, 0) x (0, 0, 1) in component "VS-MGE20 Case Assembly"
sketch "スケッチ60" plane through (0, -17, 0) normal (0, 1, 0) x (1, 0, 0) in component "VS-MGE20 Case Assembly"
  line L0 (-58, -5.3) -> (-25, -5.3)
  line L1 (-25, -5.3) -> (-25, -0.3)
  line L2 (-25, -0.3) -> (-58, -0.3)
  line L3 (-58, -0.3) -> (-58, -5.3)
extrude "押し出し71" add sketch "スケッチ60" against normal blind 2 separate body makes body 14 in component "VS-MGE20 Case Assembly"
ref_plane "作業平面59" through (0, 0, 2.8) normal (0, 0, 1) x (1, 0, 0) in component "VS-MGE20 Case Assembly"
sketch "スケッチ61" plane through (0, 0, 2.8) normal (0, 0, 1) x (1, 0, 0) in component "VS-MGE20 Case Assembly"
  line L0 (-30, -21) -> (-20, -21)
  line L1 (-20, -21) -> (-20, -20)
  line L2 (-20, -20) -> (-30, -20)
  line L3 (-30, -20) -> (-30, -21)
  line L4 (-30, -16) -> (-20, -16)
  line L5 (-20, -16) -> (-20, -15)
  line L6 (-20, -15) -> (-30, -15)
  line L7 (-30, -15) -> (-30, -16)
extrude "押し出し72" add sketch "スケッチ61" along normal blind 3.2 separate body contours L0 L1 L2 L3 makes body 15 in component "VS-MGE20 Case Assembly"
extrude "押し出し73" add sketch "スケッチ61" along normal blind 3.2 separate body contours L4 L5 L6 L7 makes body 16 in component "VS-MGE20 Case Assembly"
ref_plane "作業平面60" through (0, 0, -30) normal (0, 0, 1) x (1, 0, 0) in component "VS-MGE20 Case Assembly"
sketch "スケッチ62" plane through (0, 0, -30) normal (0, 0, 1) x (1, 0, 0) in component "VS-MGE20 Case Assembly"
  line L0 (84.2, -61.7) -> (89, -61.7)
  line L1 (89, -61.7) -> (89, -42)
  line L2 (89, -42) -> (84.2, -42)
  line L3 (84.2, -42) -> (84.2, -61.7)
extrude "押し出し74" add sketch "スケッチ62" along normal blind 42.9 separate body makes body 17 in component "VS-MGE20 Case Assembly"
ref_plane "作業平面61" through (0, -42, 0) normal (0, 1, 0) x (0, 0, 1) in component "VS-MGE20 Case Assembly"
sketch "スケッチ63" plane through (0, -42, 0) normal (0, 1, 0) x (1, 0, 0) in component "VS-MGE20 Case Assembly"
  circle A0 centre (58, -2.8) radius 3.2
extrude "押し出し75" add sketch "スケッチ63" along normal blind 3 separate body makes body 18 in component "VS-MGE20 Case Assembly"
ref_plane "作業平面62" through (0, -39, 0) normal (0, 1, 0) x (0, 0, 1) in component "VS-MGE20 Case Assembly"
sketch "スケッチ64" plane through (0, -39, 0) normal (0, 1, 0) x (1, 0, 0) in component "VS-MGE20 Case Assembly"
  line L0 (55.8345, -1.5507) -> (39.3345, -30.1507)
  line L1 (39.3345, -30.1507) -> (43.6655, -32.6493)
  line L2 (43.6655, -32.6493) -> (60.1655, -4.0493)
  line L3 (60.1655, -4.0493) -> (55.8345, -1.5507)
extrude "押し出し76" add sketch "スケッチ64" against normal blind 2 separate body makes body 19 in component "VS-MGE20 Case Assembly"
ref_plane "作業平面63" through (0, -39, 0) normal (0, 1, 0) x (0, 0, 1) in component "VS-MGE20 Case Assembly"
sketch "スケッチ65" plane through (0, -39, 0) normal (0, 1, 0) x (1, 0, 0) in component "VS-MGE20 Case Assembly"
  line L0 (58, -0.3) -> (26, -0.3)
  line L1 (26, -0.3) -> (26, -5.3)
  line L2 (26, -5.3) -> (58, -5.3)
  line L3 (58, -5.3) -> (58, -0.3)
extrude "押し出し77" add sketch "スケッチ65" against normal blind 2 separate body makes body 20 in component "VS-MGE20 Case Assembly"
ref_plane "作業平面64" through (0, 0, 2.8) normal (0, 0, 1) x (1, 0, 0) in component "VS-MGE20 Case Assembly"
sketch "スケッチ66" plane through (0, 0, 2.8) normal (0, 0, 1) x (1, 0, 0) in component "VS-MGE20 Case Assembly"
  line L0 (21, -43) -> (31, -43)
  line L1 (31, -43) -> (31, -42)
  line L2 (31, -42) -> (21, -42)
  line L3 (21, -42) -> (21, -43)
  line L4 (21, -38) -> (31, -38)
  line L5 (31, -38) -> (31, -37)
  line L6 (31, -37) -> (21, -37)
  line L7 (21, -37) -> (21, -38)
extrude "押し出し78" add sketch "スケッチ66" along normal blind 3.2 separate body contours L0 L1 L2 L3 makes body 21 in component "VS-MGE20 Case Assembly"
extrude "押し出し79" add sketch "スケッチ66" along normal blind 3.2 separate body contours L4 L5 L6 L7 makes body 22 in component "VS-MGE20 Case Assembly"
ref_plane "作業平面65" through (0, 0, -33) normal (0, 0, 1) x (1, 0, 0) in component "VS-MGE20 Case Assembly"
sketch "スケッチ67" plane through (0, 0, -33) normal (0, 0, 1) x (1, 0, 0) in component "VS-MGE20 Case Assembly"
  circle A0 centre (-51.5, -37) radius 17
  circle A1 centre (-51.5, -24) radius 17
  circle A2 centre (51.5, -58) radius 17
  circle A3 centre (51.5, -47) radius 17
ref_plane "作業平面66" through (0, -19, 0) normal (0, 1, 0) x (0, 0, 1) in component "VS-MGE20 Case Assembly"
sketch "スケッチ68" plane through (0, -19, 0) normal (0, 1, 0) x (1, 0, 0) in component "VS-MGE20 Case Assembly"
  circle A0 centre (-25, -2.8) radius 15
ref_plane "作業平面67" through (0, -41, 0) normal (0, 1, 0) x (0, 0, 1) in component "VS-MGE20 Case Assembly"
sketch "スケッチ69" plane through (0, -41, 0) normal (0, 1, 0) x (1, 0, 0) in component "VS-MGE20 Case Assembly"
  circle A0 centre (26, -2.8) radius 15
ref_plane "作業平面68" through (0, 0, -1.1) normal (0, 0, 1) x (1, 0, 0) in component "VS-MGE20 Case Assembly"
sketch "スケッチ70" plane through (0, 0, -1.1) normal (0, 0, 1) x (1, 0, 0) in component "VS-MGE20 Case Assembly"
  circle A0 centre (-25, -20) radius 3.5
extrude "押し出し88" add sketch "スケッチ70" along normal blind 0.8 separate body makes body 23 in component "VS-MGE20 Case Assembly"
ref_plane "作業平面69" through (0, 0, -1.1) normal (0, 0, 1) x (1, 0, 0) in component "VS-MGE20 Case Assembly"
sketch "スケッチ71" plane through (0, 0, -1.1) normal (0, 0, 1) x (1, 0, 0) in component "VS-MGE20 Case Assembly"
  circle A0 centre (26, -42) radius 2.8
extrude "押し出し89" add sketch "スケッチ71" along normal blind 0.8 separate body makes body 24 in component "VS-MGE20 Case Assembly"
ref_plane "作業平面70" through (0, 0, -68) normal (0, 0, 1) x (1, 0, 0) in component "VS-MGE20 Case Assembly"
sketch "スケッチ72" plane through (0, 0, -68) normal (0, 0, 1) x (1, 0, 0) in component "VS-MGE20 Case Assembly"
  line L0 (-54, -76) -> (54, -76)
  line L1 (54, -76) -> (54, 76)
  line L2 (54, 76) -> (-54, 76)
  line L3 (-54, 76) -> (-54, -76)
  line L4 (-49, -71) -> (49, -71)
  line L5 (49, -71) -> (49, 71)
  line L6 (49, 71) -> (-49, 71)
  line L7 (-49, 71) -> (-49, -71)
ref_plane "作業平面71" through (0, 0, -20) normal (0, 0, 1) x (1, 0, 0) in component "VS-MGE20 Case Assembly"
sketch "スケッチ73" plane through (0, 0, -20) normal (0, 0, 1) x (1, 0, 0) in component "VS-MGE20 Case Assembly"
  line L0 (-54, -76) -> (54, -76)
  line L1 (54, -76) -> (54, -61.5)
  line L2 (54, -61.5) -> (-54, -61.5)
  line L3 (-54, -61.5) -> (-54, -76)
  line L4 (-47, -71) -> (-33, -71)
  line L5 (-33, -71) -> (-33, -66.6)
  line L6 (-33, -66.6) -> (-47, -66.6)
  line L7 (-47, -66.6) -> (-47, -71)
  line L8 (-7, -71) -> (7, -71)
  line L9 (7, -71) -> (7, -66.6)
  line L10 (7, -66.6) -> (-7, -66.6)
  line L11 (-7, -66.6) -> (-7, -71)
  line L12 (33, -71) -> (47, -71)
  line L13 (47, -71) -> (47, -66.6)
  line L14 (47, -66.6) -> (33, -66.6)
  line L15 (33, -66.6) -> (33, -71)
  line L16 (-47, -63.5) -> (-33, -63.5)
  line L17 (-33, -63.5) -> (-33, -59.1)
  line L18 (-33, -59.1) -> (-47, -59.1)
  line L19 (-47, -59.1) -> (-47, -63.5)
ref_plane "作業平面72" through (0, 0, -33) normal (0, 0, 1) x (1, 0, 0) in component "VS-MGE20 Case Assembly"
sketch "スケッチ74" plane through (0, 0, -33) normal (0, 0, 1) x (1, 0, 0) in component "VS-MGE20 Case Assembly"
  line L0 (-92, -43) -> (-42, -43)
  line L1 (-42, -43) -> (-42, -18)
  line L2 (-42, -18) -> (-92, -18)
  line L3 (-92, -18) -> (-92, -43)
  line L4 (-56.5, -38.7) -> (-48.5, -38.7)
  line L5 (-48.5, -38.7) -> (-48.5, -35.3)
  line L6 (-48.5, -35.3) -> (-56.5, -35.3)
  line L7 (-56.5, -35.3) -> (-56.5, -38.7)
  line L8 (-56.5, -25.7) -> (-48.5, -25.7)
  line L9 (-48.5, -25.7) -> (-48.5, -22.3)
  line L10 (-48.5, -22.3) -> (-56.5, -22.3)
  line L11 (-56.5, -22.3) -> (-56.5, -25.7)
extrude "押し出し92" add sketch "スケッチ74" along normal blind 3 separate body makes body 25 in component "VS-MGE20 Case Assembly"
ref_plane "作業平面73" through (0, 0, -33) normal (0, 0, 1) x (1, 0, 0) in component "VS-MGE20 Case Assembly"
sketch "スケッチ75" plane through (0, 0, -33) normal (0, 0, 1) x (1, 0, 0) in component "VS-MGE20 Case Assembly"
  line L0 (42, -65) -> (92, -65)
  line L1 (92, -65) -> (92, -40)
  line L2 (92, -40) -> (42, -40)
  line L3 (42, -40) -> (42, -65)
  line L4 (48.5, -59.7) -> (56.5, -59.7)
  line L5 (56.5, -59.7) -> (56.5, -56.3)
  line L6 (56.5, -56.3) -> (48.5, -56.3)
  line L7 (48.5, -56.3) -> (48.5, -59.7)
  line L8 (48.5, -48.7) -> (56.5, -48.7)
  line L9 (56.5, -48.7) -> (56.5, -45.3)
  line L10 (56.5, -45.3) -> (48.5, -45.3)
  line L11 (48.5, -45.3) -> (48.5, -48.7)
extrude "押し出し93" add sketch "スケッチ75" along normal blind 3 separate body makes body 26 in component "VS-MGE20 Case Assembly"
ref_plane "作業平面74" through (0, 0, -34) normal (0, 0, 1) x (1, 0, 0) in component "VS-MGE20 Case Assembly"
sketch "スケッチ76" plane through (0, 0, -34) normal (0, 0, 1) x (1, 0, 0) in component "VS-MGE20 Case Assembly"
  line L0 (-56.5, -38.7) -> (-48.5, -38.7)
  line L1 (-48.5, -38.7) -> (-48.5, -35.3)
  line L2 (-48.5, -35.3) -> (-56.5, -35.3)
  line L3 (-56.5, -35.3) -> (-56.5, -38.7)
  line L4 (-56.5, -25.7) -> (-48.5, -25.7)
  line L5 (-48.5, -25.7) -> (-48.5, -22.3)
  line L6 (-48.5, -22.3) -> (-56.5, -22.3)
  line L7 (-56.5, -22.3) -> (-56.5, -25.7)
ref_plane "作業平面75" through (0, 0, -34) normal (0, 0, 1) x (1, 0, 0) in component "VS-MGE20 Case Assembly"
sketch "スケッチ77" plane through (0, 0, -34) normal (0, 0, 1) x (1, 0, 0) in component "VS-MGE20 Case Assembly"
  line L0 (48.5, -59.7) -> (56.5, -59.7)
  line L1 (56.5, -59.7) -> (56.5, -56.3)
  line L2 (56.5, -56.3) -> (48.5, -56.3)
  line L3 (48.5, -56.3) -> (48.5, -59.7)
  line L4 (48.5, -48.7) -> (56.5, -48.7)
  line L5 (56.5, -48.7) -> (56.5, -45.3)
  line L6 (56.5, -45.3) -> (48.5, -45.3)
  line L7 (48.5, -45.3) -> (48.5, -48.7)
ref_plane "作業平面76" through (0, -19, 0) normal (0, 1, 0) x (0, 0, 1) in component "VS-MGE20 Case Assembly"
sketch "スケッチ78" plane through (0, -19, 0) normal (0, 1, 0) x (1, 0, 0) in component "VS-MGE20 Case Assembly"
  circle A0 centre (-25, -2.8) radius 1.5
extrude "押し出し96" add sketch "スケッチ78" along normal blind 2 separate body makes body 27 in component "VS-MGE20 Case Assembly"
ref_plane "作業平面77" through (0, -19, 0) normal (0, 1, 0) x (0, 0, 1) in component "VS-MGE20 Case Assembly"
sketch "スケッチ79" plane through (0, -19, 0) normal (0, 1, 0) x (1, 0, 0) in component "VS-MGE20 Case Assembly"
  circle A0 centre (26, -2.8) radius 1.5
ref_plane "作業平面78" through (0, 0, -68) normal (0, 0, 1) x (1, 0, 0) in component "VS-MGE20 Case Assembly"
sketch "スケッチ80" plane through (0, 0, -68) normal (0, 0, 1) x (1, 0, 0) in component "VS-MGE20 Case Assembly"
  line L0 (-54, -76) -> (54, -76)
  line L1 (54, -76) -> (54, 76)
  line L2 (54, 76) -> (-54, 76)
  line L3 (-54, 76) -> (-54, -76)
  line L4 (-49, -71) -> (49, -71)
  line L5 (49, -71) -> (49, 71)
  line L6 (49, 71) -> (-49, 71)
  line L7 (-49, 71) -> (-49, -71)
extrude "押し出し98" add sketch "スケッチ80" along normal blind 48 separate body makes body 28 in component "VS-MGE20 Case Assembly"
ref_plane "作業平面79" through (0, 0, -34) normal (0, 0, 1) x (1, 0, 0) in component "VS-MGE20 Case Assembly"
sketch "スケッチ81" plane through (0, 0, -34) normal (0, 0, 1) x (1, 0, 0) in component "VS-MGE20 Case Assembly"
  line L0 (-56.5, -38.7) -> (-48.5, -38.7)
  line L1 (-48.5, -38.7) -> (-48.5, -35.3)
  line L2 (-48.5, -35.3) -> (-56.5, -35.3)
  line L3 (-56.5, -35.3) -> (-56.5, -38.7)
  line L4 (-56.5, -25.7) -> (-48.5, -25.7)
  line L5 (-48.5, -25.7) -> (-48.5, -22.3)
  line L6 (-48.5, -22.3) -> (-56.5, -22.3)
  line L7 (-56.5, -22.3) -> (-56.5, -25.7)
  line L8 (48.5, -59.7) -> (56.5, -59.7)
  line L9 (56.5, -59.7) -> (56.5, -56.3)
  line L10 (56.5, -56.3) -> (48.5, -56.3)
  line L11 (48.5, -56.3) -> (48.5, -59.7)
  line L12 (48.5, -48.7) -> (56.5, -48.7)
  line L13 (56.5, -48.7) -> (56.5, -45.3)
  line L14 (56.5, -45.3) -> (48.5, -45.3)
  line L15 (48.5, -45.3) -> (48.5, -48.7)
extrude "押し出し99" cut sketch "スケッチ81" along normal blind 16 contours L8 L9 L10 L11 bodies 28 in component "VS-MGE20 Case Assembly"
ref_plane "作業平面80" through (0, 0, -34) normal (0, 0, 1) x (1, 0, 0) in component "VS-MGE20 Case Assembly"
sketch "スケッチ82" plane through (0, 0, -34) normal (0, 0, 1) x (1, 0, 0) in component "VS-MGE20 Case Assembly"
  line L0 (-56.5, -38.7) -> (-48.5, -38.7)
  line L1 (-48.5, -38.7) -> (-48.5, -35.3)
  line L2 (-48.5, -35.3) -> (-56.5, -35.3)
  line L3 (-56.5, -35.3) -> (-56.5, -38.7)
  line L4 (-56.5, -25.7) -> (-48.5, -25.7)
  line L5 (-48.5, -25.7) -> (-48.5, -22.3)
  line L6 (-48.5, -22.3) -> (-56.5, -22.3)
  line L7 (-56.5, -22.3) -> (-56.5, -25.7)
  line L8 (48.5, -59.7) -> (56.5, -59.7)
  line L9 (56.5, -59.7) -> (56.5, -56.3)
  line L10 (56.5, -56.3) -> (48.5, -56.3)
  line L11 (48.5, -56.3) -> (48.5, -59.7)
  line L12 (48.5, -48.7) -> (56.5, -48.7)
  line L13 (56.5, -48.7) -> (56.5, -45.3)
  line L14 (56.5, -45.3) -> (48.5, -45.3)
  line L15 (48.5, -45.3) -> (48.5, -48.7)
extrude "押し出し100" cut sketch "スケッチ82" along normal blind 16 contours L0 L1 L2 L3 bodies 28 in component "VS-MGE20 Case Assembly"
extrude "押し出し101" cut sketch "スケッチ82" along normal blind 16 contours L8 L9 L10 L11 bodies 28 in component "VS-MGE20 Case Assembly"
extrude "押し出し102" cut sketch "スケッチ82" along normal blind 16 contours L4 L5 L6 L7 bodies 28 in component "VS-MGE20 Case Assembly"
extrude "押し出し103" cut sketch "スケッチ82" along normal blind 16 contours L12 L13 L14 L15 bodies 28 in component "VS-MGE20 Case Assembly"
ref_plane "作業平面81" through (0, 0, -20) normal (0, 0, 1) x (1, 0, 0) in component "VS-MGE20 Case Assembly"
sketch "スケッチ83" plane through (0, 0, -20) normal (0, 0, 1) x (1, 0, 0) in component "VS-MGE20 Case Assembly"
  line L0 (-54, -76) -> (54, -76)
  line L1 (54, -76) -> (54, -61.5)
  line L2 (54, -61.5) -> (-54, -61.5)
  line L3 (-54, -61.5) -> (-54, -76)
  line L4 (-47, -71) -> (-33, -71)
  line L5 (-33, -71) -> (-33, -66.6)
  line L6 (-33, -66.6) -> (-47, -66.6)
  line L7 (-47, -66.6) -> (-47, -71)
  line L8 (33, -71) -> (47, -71)
  line L9 (47, -71) -> (47, -66.6)
  line L10 (47, -66.6) -> (33, -66.6)
  line L11 (33, -66.6) -> (33, -71)
extrude "押し出し104" add sketch "スケッチ83" along normal blind 20 separate body makes body 29 in component "VS-MGE20 Case Assembly"
ref_plane "作業平面82" through (0, -41, 0) normal (0, 1, 0) x (0, 0, 1) in component "VS-MGE20 Case Assembly"
sketch "スケッチ84" plane through (0, -41, 0) normal (0, 1, 0) x (1, 0, 0) in component "VS-MGE20 Case Assembly"
  circle A0 centre (26, -2.8) radius 1.5
extrude "押し出し105" add sketch "スケッチ84" along normal blind 2 separate body makes body 30 in component "VS-MGE20 Case Assembly"
copy_body "CutPasteBodies1" bodies 1 removing the originals makes body 31 in component "PRINT 01 Front guard"
copy_body "CutPasteBodies1'" bodies 2 removing the originals makes body 32 in component "PRINT 02 Upper bridge"
copy_body "CutPasteBodies1''" bodies 29 removing the originals makes body 33 in component "PRINT 03 Lower bridge"
copy_body "CutPasteBodies1'''" bodies 25 removing the originals makes body 34 in component "PRINT 04 Call servo pod base"
copy_body "CutPasteBodies1''''" bodies 26 removing the originals makes body 35 in component "PRINT 05 End servo pod base"
copy_body "CutPasteBodies1'''''" bodies 11 removing the originals makes body 36 in component "PRINT 06 Call pod retainer"
copy_body "CutPasteBodies1''''''" bodies 17 removing the originals makes body 37 in component "PRINT 07 End pod retainer"
copy_body "CutPasteBodies1'''''''" bodies 28 removing the originals makes body 38 in component "PRINT 08 Charger cradle frame"
copy_body "CutPasteBodies1''''''''" bodies 4 removing the originals makes body 39 in component "PRINT 09 Call pusher shaft"
copy_body "CutPasteBodies1'''''''''" bodies 5 removing the originals makes body 40 in component "PRINT 10 Call stop collar"
copy_body "CutPasteBodies1''''''''''" bodies 6 removing the originals makes body 41 in component "PRINT 11 Call guide ring"
copy_body "CutPasteBodies1'''''''''''" bodies 8 removing the originals makes body 42 in component "PRINT 12 End pusher shaft"
copy_body "CutPasteBodies1''''''''''''" bodies 9 removing the originals makes body 43 in component "PRINT 13 End stop collar"
copy_body "CutPasteBodies1'''''''''''''" bodies 10 removing the originals makes body 44 in component "PRINT 14 End guide ring"
copy_body "CutPasteBodies1''''''''''''''" bodies 12 removing the originals makes body 45 in component "PRINT 15 Call servo horn"
copy_body "CutPasteBodies1'''''''''''''''" bodies 18 removing the originals makes body 46 in component "PRINT 16 End servo horn"
copy_body "CutPasteBodies1''''''''''''''''" bodies 13 removing the originals makes body 47 in component "PRINT 17 Call servo arm HOME"
copy_body "CutPasteBodies1'''''''''''''''''" bodies 19 removing the originals makes body 48 in component "PRINT 18 End servo arm HOME"
copy_body "CutPasteBodies1''''''''''''''''''" bodies 15 removing the originals makes body 49 in component "PRINT 19 Call fork cheek A"
copy_body "CutPasteBodies1'''''''''''''''''''" bodies 16 removing the originals makes body 50 in component "PRINT 20 Call fork cheek B"
copy_body "CutPasteBodies1''''''''''''''''''''" bodies 21 removing the originals makes body 51 in component "PRINT 21 End fork cheek A"
copy_body "CutPasteBodies1'''''''''''''''''''''" bodies 22 removing the originals makes body 52 in component "PRINT 22 End fork cheek B"
copy_body "CutPasteBodies1''''''''''''''''''''''" bodies 27 removing the originals makes body 53 in component "PRINT 23 Call follower pin"
copy_body "CutPasteBodies1'''''''''''''''''''''''" bodies 30 removing the originals makes body 54 in component "PRINT 24 End follower pin"
copy_body "CutPasteBodies1''''''''''''''''''''''''" bodies 23 removing the originals makes body 55 in component "TPU 01 Call button pad"
copy_body "CutPasteBodies1'''''''''''''''''''''''''" bodies 24 removing the originals makes body 56 in component "TPU 02 End button pad"
copy_body "CutPasteBodies1''''''''''''''''''''''''''" bodies 3 removing the originals makes body 57 in component "REFERENCE ONLY - DO NOT PRINT"
copy_body "CutPasteBodies2" bodies 7 removing the originals makes body 58 in component "REFERENCE ONLY - DO NOT PRINT"
copy_body "CutPasteBodies3" bodies 14 removing the originals makes body 59 in component "REFERENCE ONLY - DO NOT PRINT"
copy_body "CutPasteBodies4" bodies 20 removing the originals makes body 60 in component "REFERENCE ONLY - DO NOT PRINT"
ref_plane "作業平面1" through (0, 0, 3) normal (0, 0, 1) x (1, 0, 0) in component "PRINT 01 Front guard"
sketch "スケッチ1 (2)" plane through (0, 0, 3) normal (0, 0, 1) x (1, 0, 0) in component "PRINT 01 Front guard"
  circle A0 centre (25, -20) radius 7
  line L0 (-10, -30) -> (10, -30)
  line L1 (10, -30) -> (10, -10)
  line L2 (10, -10) -> (-10, -10)
  line L3 (-10, -10) -> (-10, -30)
  circle A1 centre (-25, -42) radius 7
  circle A2 centre (0, -42) radius 7
extrude "Manual button access openings" cut sketch "スケッチ1 (2)" against normal blind 14 bodies 31 in component "PRINT 01 Front guard"
ref_plane "作業平面1" through (0, 0, -5) normal (0, 0, 1) x (1, 0, 0)
sketch "スケッチ1 (3)" plane through (0, 0, -5) normal (0, 0, 1) x (1, 0, 0)
  line L0 (-76, -27) -> (-40, -27)
  line L1 (-40, -27) -> (-40, -9)
  line L2 (-40, -9) -> (-76, -9)
  line L3 (-76, -9) -> (-76, -27)
  line L4 (-70.75, -24.75) -> (-45.25, -24.75)
  line L5 (-45.25, -24.75) -> (-45.25, -11.25)
  line L6 (-45.25, -11.25) -> (-70.75, -11.25)
  line L7 (-70.75, -11.25) -> (-70.75, -24.75)
  circle A0 centre (-72, -18) radius 1.3
  circle A1 centre (-44, -18) radius 1.3
  line L8 (-61, -13) -> (-55, -13)
  line L9 (-55, -13) -> (-55, -7)
  line L10 (-55, -7) -> (-61, -7)
  line L11 (-61, -7) -> (-61, -13)
  line L12 (40, -49.5) -> (76, -49.5)
  line L13 (76, -49.5) -> (76, -31.5)
  line L14 (76, -31.5) -> (40, -31.5)
  line L15 (40, -31.5) -> (40, -49.5)
  line L16 (45.25, -47.25) -> (70.75, -47.25)
  line L17 (70.75, -47.25) -> (70.75, -33.75)
  line L18 (70.75, -33.75) -> (45.25, -33.75)
  line L19 (45.25, -33.75) -> (45.25, -47.25)
  circle A2 centre (44, -40.5) radius 1.3
  circle A3 centre (72, -40.5) radius 1.3
  line L20 (55, -35.5) -> (61, -35.5)
  line L21 (61, -35.5) -> (61, -29.5)
  line L22 (61, -29.5) -> (55, -29.5)
  line L23 (55, -29.5) -> (55, -35.5)
extrude "SG90 paired mounting plates, M2 clearance and cable notches" add sketch "スケッチ1 (3)" along normal blind 2 separate body makes body 61 at (-59, -21, -5) makes body 62 at (57, -43.5, -5)
ref_plane "作業平面2" through (0, 0, 3) normal (0, 0, 1) x (1, 0, 0) in component "PRINT 01 Front guard"
sketch "スケッチ2 (2)" plane through (0, 0, 3) normal (0, 0, 1) x (1, 0, 0) in component "PRINT 01 Front guard"
  line L0 (-35, -52) -> (-15, -52)
  line L1 (-15, -52) -> (-15, -32)
  line L2 (-15, -32) -> (-35, -32)
  line L3 (-35, -32) -> (-35, -52)
extrude "Square manual opening over playback scallops 20x20" cut sketch "スケッチ2 (2)" against normal blind 14 bodies 31 in component "PRINT 01 Front guard"
component "VS-MGE20 Case Assembly" placed x (1, 0, 0) y (0, 1, 0) z (0, 0, 1) at (0, 0, 0)
component "PRINT 01 Front guard" placed x (1, 0, 0) y (0, 1, 0) z (0, 0, 1) at (0, 0, 0) in component "VS-MGE20 Case Assembly"
component "PRINT 02 Upper bridge" placed x (1, 0, 0) y (0, 1, 0) z (0, 0, 1) at (0, 0, 0) in component "VS-MGE20 Case Assembly"
component "PRINT 03 Lower bridge" placed x (1, 0, 0) y (0, 1, 0) z (0, 0, 1) at (0, 0, 0) in component "VS-MGE20 Case Assembly"
component "PRINT 04 Call servo pod base" placed x (1, 0, 0) y (0, 1, 0) z (0, 0, 1) at (0, 0, 0) in component "VS-MGE20 Case Assembly"
component "PRINT 05 End servo pod base" placed x (1, 0, 0) y (0, 1, 0) z (0, 0, 1) at (0, 0, 0) in component "VS-MGE20 Case Assembly"
component "PRINT 06 Call pod retainer" placed x (1, 0, 0) y (0, 1, 0) z (0, 0, 1) at (0, 0, 0) in component "VS-MGE20 Case Assembly"
component "PRINT 07 End pod retainer" placed x (1, 0, 0) y (0, 1, 0) z (0, 0, 1) at (0, 0, 0) in component "VS-MGE20 Case Assembly"
component "PRINT 08 Charger cradle frame" placed x (1, 0, 0) y (0, 1, 0) z (0, 0, 1) at (0, 0, 0) in component "VS-MGE20 Case Assembly"
component "PRINT 09 Call pusher shaft" placed x (1, 0, 0) y (0, 1, 0) z (0, 0, 1) at (0, 0, 0) in component "VS-MGE20 Case Assembly"
component "PRINT 10 Call stop collar" placed x (1, 0, 0) y (0, 1, 0) z (0, 0, 1) at (0, 0, 0) in component "VS-MGE20 Case Assembly"
component "PRINT 11 Call guide ring" placed x (1, 0, 0) y (0, 1, 0) z (0, 0, 1) at (0, 0, 0) in component "VS-MGE20 Case Assembly"
component "PRINT 12 End pusher shaft" placed x (1, 0, 0) y (0, 1, 0) z (0, 0, 1) at (0, 0, 0) in component "VS-MGE20 Case Assembly"
component "PRINT 13 End stop collar" placed x (1, 0, 0) y (0, 1, 0) z (0, 0, 1) at (0, 0, 0) in component "VS-MGE20 Case Assembly"
component "PRINT 14 End guide ring" placed x (1, 0, 0) y (0, 1, 0) z (0, 0, 1) at (0, 0, 0) in component "VS-MGE20 Case Assembly"
component "PRINT 15 Call servo horn" placed x (1, 0, 0) y (0, 1, 0) z (0, 0, 1) at (0, 0, 0) in component "VS-MGE20 Case Assembly"
component "PRINT 16 End servo horn" placed x (1, 0, 0) y (0, 1, 0) z (0, 0, 1) at (0, 0, 0) in component "VS-MGE20 Case Assembly"
component "PRINT 17 Call servo arm HOME" placed x (1, 0, 0) y (0, 1, 0) z (0, 0, 1) at (0, 0, 0) in component "VS-MGE20 Case Assembly"
component "PRINT 18 End servo arm HOME" placed x (1, 0, 0) y (0, 1, 0) z (0, 0, 1) at (0, 0, 0) in component "VS-MGE20 Case Assembly"
component "PRINT 19 Call fork cheek A" placed x (1, 0, 0) y (0, 1, 0) z (0, 0, 1) at (0, 0, 0) in component "VS-MGE20 Case Assembly"